key-turner_v0.1 (Autodesk Fusion 360 design; units mm, degrees)
part number: 2026-11-10-13-21-37-774
Autodesk Fusion 360 part; units mm, degrees
sketch "PaddleProfile" plane through (0, 0, 0) normal (0, 1, 0) x (1, 0, 0)
  line L0 (-47.5, 0) -> (47.5, 0)
  line L1 (47.5, 0) -> (47.5, -66)
  line L2 (47.5, -66) -> (-47.5, -66)
  line L3 (-47.5, -66) -> (-47.5, 0)
  dimension "d14" = 95
  dimension "d15" = 66
  constraint horizontal L0
  constraint horizontal L2
  constraint vertical L1
  constraint vertical L3
  constraint midpoint origin L0
  measures "d14" distance of L0.start L0.end
  measures "d15" distance of L0.end L1.end
extrude "Paddle" add sketch "PaddleProfile" along normal mid plane 18
fillet "TopCornerRounds" radius 8 2 edges at (47.5, 0, 66) (-47.5, 0, 66)
chamfer "BaseCornerChamfers" distance 3 angle 45 2 edges at (47.5, 0, 0) (-47.5, 0, 0) tangent chain off
sketch "FingerHole" plane through (0, 0, 0) normal (0, 1, 0) x (1, 0, 0)
  circle A0 centre (0, -17) radius 11
  line L0 (7.7782, -24.7782) -> (0, -32.5563)
  line L1 (0, -32.5563) -> (-7.7782, -24.7782)
  line L2 (-7.7782, -24.7782) -> (7.7782, -24.7782)
  line L3 (0, 0) -> (0, -17) construction
  dimension "d21" = 22
  dimension "d22" = 17
  dimension "d23" = 15.5563
  constraint coincident A0 L0.start
  constraint coincident A0 L1.end
  constraint tangent A0 L0
  constraint tangent A0 L1
  constraint horizontal L2
  constraint vertical L3
  constraint coincident A0.centre L3.end
  measures "d21" diameter of A0
  measures "d22" distance of L3.start A0.centre
  measures "d23" distance of A0.centre L0.end
extrude "TeardropFingerHole" cut sketch "FingerHole" along normal mid plane 20
ref_plane "WorkPlane1" through (0, 0, 66) normal (0, 0, 1) x (1, 0, 0)
sketch "KeySlot" plane through (0, 0, 66) normal (0, 0, 1) x (1, 0, 0)
  line L0 (-16, -1.2) -> (16, -1.2)
  line L1 (16, -1.2) -> (16, 1.2)
  line L2 (16, 1.2) -> (-16, 1.2)
  line L3 (-16, 1.2) -> (-16, -1.2)
  line L4 (-16, -1.2) -> (16, 1.2) construction
  dimension "d28" = 32
  dimension "d29" = 2.4
  constraint horizontal L0
  constraint vertical L1
  constraint horizontal L2
  constraint vertical L3
  constraint midpoint origin L4
  measures "d28" horizontal distance of L0.start L0.end
  measures "d29" vertical distance of L0.end L1.end
extrude "KeySlotCut" cut sketch "KeySlot" against normal blind 18
chamfer "SlotLeadIn" distance 1 angle 45 4 edges at (0, -1.2, 66) (16, 0, 66) (0, 1.2, 66) (-16, 0, 66) tangent chain off
fillet "OuterComfortFillets" radius 2 56 edges at (0, -9, 66) (-45.1569, -9, 63.6569) (-47.5, -9, 30.5) (45.1569, -9, 63.6569) (47.5, -9, 30.5) (0, 9, 66) (45.1569, 9, 63.6569) (47.5, 9, 30.5) (-45.1569, 9, 63.6569) (-47.5, 9, 30.5) (-46, 9, 1.5) (-46, -9, 1.5) (-47.5, 0, 3) (46, -9, 1.5) (47.5, -9, 30.5) (45.1569, -9, 63.6569) (0, -9, 66) (-45.1569, -9, 63.6569) (-47.5, -9, 30.5) (45.1569, -9, 63.6569) (47.5, -9, 30.5) (0, -9, 66) (-45.1569, -9, 63.6569) (-47.5, -9, 30.5) (-45.1569, -9, 63.6569) (0, -9, 66) (45.1569, -9, 63.6569) (47.5, -9, 30.5) (-47.5, -9, 30.5) (-47.5, -9, 30.5) (-45.1569, -9, 63.6569) (0, -9, 66) (45.1569, -9, 63.6569) (47.5, -9, 30.5) (46, 9, 1.5) (47.5, 0, 3) (-45.1569, 9, 63.6569) (-47.5, 9, 30.5) (0, 9, 66) (45.1569, 9, 63.6569) (47.5, 9, 30.5) (45.1569, 9, 63.6569) (0, 9, 66) (-45.1569, 9, 63.6569) (-47.5, 9, 30.5) (47.5, 9, 30.5) (47.5, 9, 30.5) (45.1569, 9, 63.6569) (0, 9, 66) (-45.1569, 9, 63.6569) (-47.5, 9, 30.5) (-47.5, 9, 30.5) (-45.1569, 9, 63.6569) (0, 9, 66) (45.1569, 9, 63.6569) (47.5, 9, 30.5)
fillet "FingerHoleFillets" radius 1.5 19 edges at (3.8891, 9, 28.6673) (0, 9, 6) (-3.8891, 9, 28.6673) (-3.8891, 9, 28.6673) (0, 9, 6) (3.8891, 9, 28.6673) (0, 9, 6) (3.8891, 9, 28.6673) (-3.8891, 9, 28.6673) (-3.8891, -9, 28.6673) (0, -9, 6) (3.8891, -9, 28.6673) (0, 0, 32.5563) (3.8891, -9, 28.6673) (0, -9, 6) (-3.8891, -9, 28.6673) (0, -9, 6) (-3.8891, -9, 28.6673) (3.8891, -9, 28.6673)
fillet "SlotEndRounds" radius 1.1 4 edges at (-16, -1.2, 56.5) (-16, 1.2, 56.5) (16, -1.2, 56.5) (16, 1.2, 56.5)
fillet "SlotFloorFillet" radius 1 64 edges at (15.6778, 0.8778, 48) (0, 1.2, 48) (-15.6778, 0.8778, 48) (-16, 0, 48) (-15.6778, -0.8778, 48) (0, -1.2, 48) (15.6778, -0.8778, 48) (16, 0, 48) (0, 1.2, 48) (15.6778, 0.8778, 48) (16, 0, 48) (15.6778, -0.8778, 48) (0, -1.2, 48) (-15.6778, -0.8778, 48) (-16, 0, 48) (-15.6778, 0.8778, 48) (15.6778, -0.8778, 48) (16, 0, 48) (15.6778, 0.8778, 48) (0, 1.2, 48) (-15.6778, 0.8778, 48) (-16, 0, 48) (-15.6778, -0.8778, 48) (0, -1.2, 48) (16, 0, 48) (15.6778, -0.8778, 48) (0, -1.2, 48) (-15.6778, -0.8778, 48) (-16, 0, 48) (-15.6778, 0.8778, 48) (0, 1.2, 48) (15.6778, 0.8778, 48) (-15.6778, 0.8778, 48) (-16, 0, 48) (-15.6778, -0.8778, 48) (0, -1.2, 48) (15.6778, -0.8778, 48) (16, 0, 48) (15.6778, 0.8778, 48) (0, 1.2, 48) (-16, 0, 48) (-15.6778, 0.8778, 48) (0, 1.2, 48) (15.6778, 0.8778, 48) (16, 0, 48) (15.6778, -0.8778, 48) (0, -1.2, 48) (-15.6778, -0.8778, 48) (-15.6778, -0.8778, 48) (0, -1.2, 48) (15.6778, -0.8778, 48) (16, 0, 48) (15.6778, 0.8778, 48) (0, 1.2, 48) (-15.6778, 0.8778, 48) (-16, 0, 48) (0, -1.2, 48) (-15.6778, -0.8778, 48) (-16, 0, 48) (-15.6778, 0.8778, 48) (0, 1.2, 48) (15.6778, 0.8778, 48) (16, 0, 48) (15.6778, -0.8778, 48)
equation "paddle_w = 95 mm" comment "Paddle length gripped by the hand = ANSUR II hand breadth + 8-9 mm, rounded to 5 mm (M: all-subjects median 86 mm)"
equation "paddle_h = 66 mm" comment "Paddle height: holds key slot + finger hole with >= 7 mm web between them (design estimate)"
equation "paddle_t = 18 mm" comment "Paddle thickness (rev3: 14 -> 18 mm after FE showed slot-wall bending across layers; design estimate)"
equation "key_t = 2.4 mm" comment "Key slot thickness = 2.0 mm KW1 blade thickness (single retailer listing) + 0.4 mm clearance. MEASURE YOUR KEY"
equation "key_slot_w = 32 mm" comment "Key slot width, fits the bow of common house keys (design estimate - measure your key)"
equation "key_slot_d = 18 mm" comment "Key slot depth (rev2: 24 -> 18 mm to shorten the slot-wall lips; design estimate)"
equation "slot_leadin = 1 mm" comment "45 deg chamfer around slot opening for easier insertion"
equation "finger_d = 22 mm" comment "Finger hole diameter (design estimate; no finger-breadth data in ANSUR II)"
equation "finger_z = finger_d / 2 + 6 mm" comment "Finger hole centre height: 6 mm of material under the hole"
equation "top_r = 8 mm" comment "Top corner radius"
equation "base_ch = 3 mm" comment "45 deg chamfer on bottom corners (a round here would overhang near the bed)"
equation "edge_r = 2 mm" comment "Comfort fillet on all non-bed outer edges"
equation "hole_r = 1.5 mm" comment "Comfort fillet on finger-hole edges"
equation "d14 = paddle_w"
equation "d15 = paddle_h"
equation "d16 = paddle_t"
equation "d19 = top_r"
equation "d20 = base_ch"
equation "d21 = finger_d"
equation "d22 = finger_z"
equation "d23 = finger_d / 2 * sqrt(2)"
equation "d24 = paddle_t + 2 mm"
equation "d26 = paddle_h"
equation "d28 = key_slot_w"
equation "d29 = key_t"
equation "d30 = -( key_slot_d )"
equation "d32 = slot_leadin"
equation "d34 = edge_r"
equation "d36 = hole_r"
equation "slot_end_r = key_t / 2 - 0.1 mm" comment "Radius on the slot's vertical end corners (rev: FE showed a sharp-corner stress peak)"
equation "slot_floor_r = 1 mm" comment "Fillet between slot floor and slot walls (cup-shaped floor, prints without support)"
equation "d40 = slot_end_r"
equation "d42 = slot_floor_r"
named bodies: "KeyTurner"
